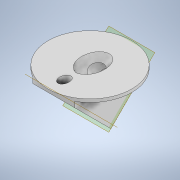
# Autodesk Inventor part: Part1
Saved by Autodesk Inventor 2022.6 (Build 266554000, 554)
## iProperties
Created: 2025-09-14
Part Number: Part1
Material: Generic
Document SubType Name: Modeling
Designer: Dragos Macovei
Density: 1 g/cm^3
Appearance: Default
Author: Dragos Macovei
Autodesk Inventor part; units mm, degrees
ref_plane "YZ Plane" through (0, 0, 0) normal (1, 0, 0) x (0, 1, 0)
ref_plane "XZ Plane" through (0, 0, 0) normal (0, 1, 0) x (-1, 0, 0)
ref_plane "XY Plane" through (0, 0, 0) normal (0, 0, 1) x (1, 0, 0)
sketch "Sketch1" plane through (0, 0, 0) normal (0, 1, 0) x (-1, 0, 0)
  circle A0 centre (0, 0) radius 55
  dimension "d0" = 110
  constraints: 1 centre point, 1 coincident
  measures "d0" diameter of A0
extrude "Extrusion1" add sketch "Sketch1" along normal blind 4
sketch "Sketch2" plane through (0, 0, 0) normal (1, 0, 0) x (0, 1, 0)
  line L0 (0, 55) -> (4, 55) projected
  line L1 (0, 55) -> (-55, 0)
  line L2 (0, -55) -> (0, 55) projected
  line L3 (-55, 0) -> (0, -55)
  line L4 (-69.7483, 0) -> (0, 0)
  dimension "d3" = 90
  constraints: 6 end point, 2 point on line, 1 horizontal
  measures "d3" angle of L3 L1
extrude "Extrusion2" add sketch "Sketch2" along normal mid plane 55
sketch "Sketch3" plane through (0, 4, 0) normal (0, 1, 0) x (1, 0, 0)
  arc A0 (0, 55) -> (-27.5, 47.6314) centre (0, 0) ccw projected
  line L0 (-27.5, 55) -> (0, 55) projected
  line L1 (-27.5, 47.6314) -> (-27.5, 55) projected
  arc A1 (27.5, 47.6314) -> (0, 55) centre (0, 0) ccw projected
  line L2 (27.5, 55) -> (27.5, 47.6314) projected
  line L3 (0, 55) -> (27.5, 55) projected
  arc A2 (0, -55) -> (27.5, -47.6314) centre (0, 0) ccw projected
  line L4 (27.5, -55) -> (0, -55) projected
  line L5 (27.5, -47.6314) -> (27.5, -55) projected
  arc A3 (-27.5, -47.6314) -> (0, -55) centre (0, 0) ccw projected
  line L6 (-27.5, -55) -> (-27.5, -47.6314) projected
  line L7 (0, -55) -> (-27.5, -55) projected
extrude "Extrusion3" cut sketch "Sketch3" against normal blind 55
sketch "Sketch4" plane through (-27.5, -55, 0) normal (0, -0.7071, 0.7071) x (1, 0, 0)
  circle A0 centre (27.5, 38.8909) radius 15
  dimension "d8" = 30
  constraints: 1 centre point, 1 coincident
  measures "d8" diameter of A0
extrude "Extrusion4" cut sketch "Sketch4" against normal blind 81
sketch "Sketch5" plane through (27.5, -55, 0) normal (0, -0.7071, -0.7071) x (-1, 0, 0)
  circle A0 centre (27.5, 38.8909) radius 2
  dimension "d11" = 4
  constraints: 1 centre point, 1 coincident
  measures "d11" diameter of A0
extrude "Extrusion5" cut sketch "Sketch5" against normal blind 81
ref_plane "Work Plane1" through (27.5, -52.1716, 2.8284) normal (0, -0.7071, -0.7071) x (-1, 0, 0)
sketch "Sketch7" plane through (27.5, -52.1716, 2.8284) normal (0, -0.7071, -0.7071) x (-1, 0, 0)
  circle A0 centre (27.5, 38.8909) radius 2 projected
  circle A1 centre (27.5, 38.8909) radius 10
  dimension "d16" = 20
  constraints: 1 centre point, 1 coincident
  measures "d16" diameter of A1
extrude "Extrusion6" cut sketch "Sketch7" against normal blind 81
fillet "Fillet1" radius 4 1 edges at (10, -24.6716, -24.6716)
sketch "Sketch8" plane through (-27.5, -55, 0) normal (0, -0.7071, 0.7071) x (1, 0, 0)
  circle A0 centre (27.5, 15) radius 2
  line L0 (0, 0) -> (55, 0) projected
  circle A1 centre (27.5, 65.5184) radius 2
  point P0 (27.5, 38.8909)
  point P1 (27.5, 0)
  dimension "d20" = 15
  dimension "d21" = 4
  constraints: 2 centre point, 1 midpoint
  measures "d20" distance of point (27.5, 0) A0.centre
  measures "d21" diameter of A0
extrude "Extrusion7" cut sketch "Sketch8" against normal blind 81 contours A1
ref_plane "Work Plane2" through (-27.5, -52.1716, -2.8284) normal (0, -0.7071, 0.7071) x (1, 0, 0)
sketch "Sketch9" plane through (-27.5, -52.1716, -2.8284) normal (0, -0.7071, 0.7071) x (1, 0, 0)
  circle A0 centre (27.5, 65.5184) radius 2 projected
  circle A1 centre (27.5, 65.5184) radius 6
  point P0 (27.5, 38.8909)
  dimension "d25" = 12
  constraints: 1 centre point, 1 coincident
  measures "d25" diameter of A1
extrude "Extrusion8" cut sketch "Sketch9" against normal blind 81 contours A0 | A1
fillet "Fillet2" radius 4 1 edges at (-6, -5.8431, 43.5)
body "Solid1"
